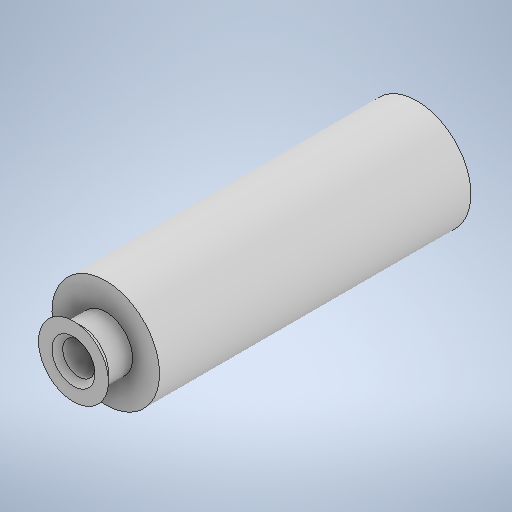
# Autodesk Inventor part: wspornik
Saved by Autodesk Inventor 2025.2 (Build 292293000, 293)
## iProperties
Created: 2025-04-07
Part Number: wspornik
Material: Ogólny
Document SubType Name: Modeling
Designer: Jan Bołtralik
Density: 1 g/cm^3
Appearance: Domyślna
Author: Jan Bołtralik
Autodesk Inventor part; units mm, degrees
ref_plane "YZ Plane" through (0, 0, 0) normal (1, 0, 0) x (0, 1, 0)
ref_plane "XZ Plane" through (0, 0, 0) normal (0, 1, 0) x (-1, 0, 0)
ref_plane "XY Plane" through (0, 0, 0) normal (0, 0, 1) x (1, 0, 0)
sketch "Szkic1" plane through (0, 0, 0) normal (0, 1, 0) x (-1, 0, 0)
  line L0 (0, 0) -> (0, -44.1429)
  line L1 (-5, -2.0558) -> (-5, -31.0558)
  line L2 (-5, -31.0558) -> (-2, -31.0558)
  line L3 (-2, -31.0558) -> (-2, -33.0558)
  line L4 (-2, -33.0558) -> (0, -33.0558)
  line L5 (-5, -2.0558) -> (-2.5, -2.0558)
  line L6 (-2.5, -2.0558) -> (-2.5, 0.1942)
  line L7 (-2.5, 0.1942) -> (-3.25, 0.9442)
  line L8 (-1.75, 0.9442) -> (0.6193, 0.9442) construction
  line L9 (-3.25, 0.9442) -> (0, 0.9442)
  line L10 (0, 0.9442) -> (0, 0)
  point P0 (0, -2.0558)
  dimension "d0" = 29
  dimension "d1" = 2
  dimension "d3" = 135
  dimension "d7" = 4
  dimension "d8" = 10
  dimension "d9" = 5
  dimension "d21" = 6.5
  dimension "d22" = 3
  constraints: 22 end point, 4 vertical, 3 horizontal, 3 perpendicular, 3 point on line
  measures "d0" distance of L1.start L1.end
  measures "d1" distance of L2.end L3.end
  measures "d3" angle of L7 L6
  measures "d7" diameter of L3 L0
  measures "d8" diameter of L1 L0
  measures "d9" diameter of L6 L0
  measures "d21" diameter of L7.end L0
  measures "d22" distance from line of L5 L7.end
revolve "Obrót1" add sketch "Szkic1" angle 360 about axis through (0, 0, 0) along (0, 0, -1)
sketch "Szkic2" plane through (0, 0, -33.0558) normal (0, 0, -1) x (-1, 0, 0)
  circle A0 centre (0, 0) radius 2 projected
hole "Otwór1" at (0, 0, -33.0558) direction (0, 0, 1) diameter 2.459 depth 8.8 tip angle 118 thread size "M3x0.5" class "6H" standard "ISO Metric profile"
sketch "Sketch3" plane through (0, 0, 0.9442) normal (0, 0, 1) x (1, 0, 0)
  point P0 (0, 0)
  point P1 (0, 0)
  constraints: 1 coincident
hole "Hole2" at (0, 0, 0.9442) direction (0, 0, -1) diameter 3 depth 5 tip angle 118 countersink diameter 4 countersink angle 90
